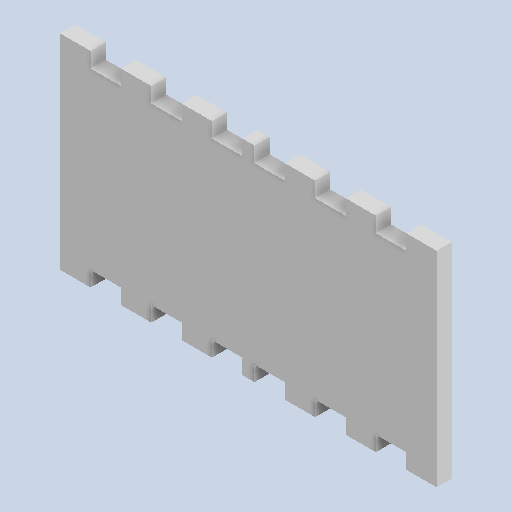
# Autodesk Inventor part: MainTop
Saved by Autodesk Inventor 2025.2 (Build 292293000, 293)
## iProperties
Created: 2025-06-25
Part Number: MainTop
Material: Generic
Document SubType Name: Modeling
Designer: ricoa
Density: 1 g/cm^3
Appearance: Default
Author: ricoa
Autodesk Inventor part; units mm, degrees
ref_plane "YZ Plane" through (0, 0, 0) normal (1, 0, 0) x (0, 1, 0)
ref_plane "XZ Plane" through (0, 0, 0) normal (0, 1, 0) x (-1, 0, 0)
ref_plane "XY Plane" through (0, 0, 0) normal (0, 0, 1) x (1, 0, 0)
sketch "Sketch1" plane through (0, 0, 0) normal (0, 0, 1) x (1, 0, 0)
  line L0 (50, 0) -> (60, 0) projected
  line L1 (30, 0) -> (40, 0) projected
  line L2 (10, 0) -> (20, 0) projected
  line L3 (-4, 0) -> (0, 0) projected
  line L4 (-24, 0) -> (-14, 0) projected
  line L5 (-44, 0) -> (-34, 0) projected
  line L6 (-64, 0) -> (-54, 0) projected
  line L7 (-44, -5) -> (-54, -5) projected
  line L8 (-44, 0) -> (-44, -5) projected
  line L9 (-54, 0) -> (-54, -5) projected
  line L10 (-64, 0) -> (-64, -5) projected
  line L11 (-24, -5) -> (-34, -5) projected
  line L12 (-24, 0) -> (-24, -5) projected
  line L13 (-34, 0) -> (-34, -5) projected
  line L14 (-4, 0) -> (-4, -5) projected
  line L15 (-4, -5) -> (-14, -5) projected
  line L16 (-14, 0) -> (-14, -5) projected
  line L17 (10, 0) -> (10, -5) projected
  line L18 (10, -5) -> (0, -5) projected
  line L19 (0, 0) -> (0, -5) projected
  line L20 (20, 0) -> (20, -5) projected
  line L21 (30, 0) -> (30, -5) projected
  line L22 (30, -5) -> (20, -5) projected
  line L23 (50, 0) -> (50, -5) projected
  line L24 (50, -5) -> (40, -5) projected
  line L25 (40, 0) -> (40, -5) projected
  line L26 (60, 0) -> (60, -5) projected
  line L27 (60, -67.5) -> (-64, -67.5) projected
  line L28 (-64, -67.5) -> (-64, 0)
  line L29 (-64, -33.75) -> (60, -33.75) construction
  line L30 (60, -67.5) -> (60, 0)
  line L31 (50, -67.5) -> (60, -67.5)
  line L32 (30, -67.5) -> (40, -67.5)
  line L33 (10, -67.5) -> (20, -67.5)
  line L34 (-4, -67.5) -> (0, -67.5)
  line L35 (-24, -67.5) -> (-14, -67.5)
  line L36 (-44, -67.5) -> (-34, -67.5)
  line L37 (-64, -67.5) -> (-54, -67.5)
  line L38 (-44, -62.5) -> (-54, -62.5)
  line L39 (-44, -67.5) -> (-44, -62.5)
  line L40 (-54, -67.5) -> (-54, -62.5)
  line L41 (-64, -67.5) -> (-64, -62.5)
  line L42 (-24, -62.5) -> (-34, -62.5)
  line L43 (-24, -67.5) -> (-24, -62.5)
  line L44 (-34, -67.5) -> (-34, -62.5)
  line L45 (-4, -67.5) -> (-4, -62.5)
  line L46 (-4, -62.5) -> (-14, -62.5)
  line L47 (-14, -67.5) -> (-14, -62.5)
  line L48 (10, -67.5) -> (10, -62.5)
  line L49 (10, -62.5) -> (0, -62.5)
  line L50 (0, -67.5) -> (0, -62.5)
  line L51 (20, -67.5) -> (20, -62.5)
  line L52 (30, -67.5) -> (30, -62.5)
  line L53 (30, -62.5) -> (20, -62.5)
  line L54 (50, -67.5) -> (50, -62.5)
  line L55 (50, -62.5) -> (40, -62.5)
  line L56 (40, -67.5) -> (40, -62.5)
  line L57 (60, -67.5) -> (60, -62.5)
  constraints: 60 end point, 26 symmetric about line, 2 vertical, 1 horizontal, 1 midpoint
extrude "Extrusion1" add sketch "Sketch1" along normal blind 5 contours L0 L26 L30 L27 L54 L55 L56 L52 L53 L51 L48 L49 L50 L45 L46 L47 L43 L42 L44 L39 L38 L40 L28 L10 L6 L9 L7 L8 L5 L13 L11 L12 L4 L16 L15 L14 L3 L19 L18 L17 L2 L20 L22 L21 L1 L25 L24 L23
body "Solid1"
